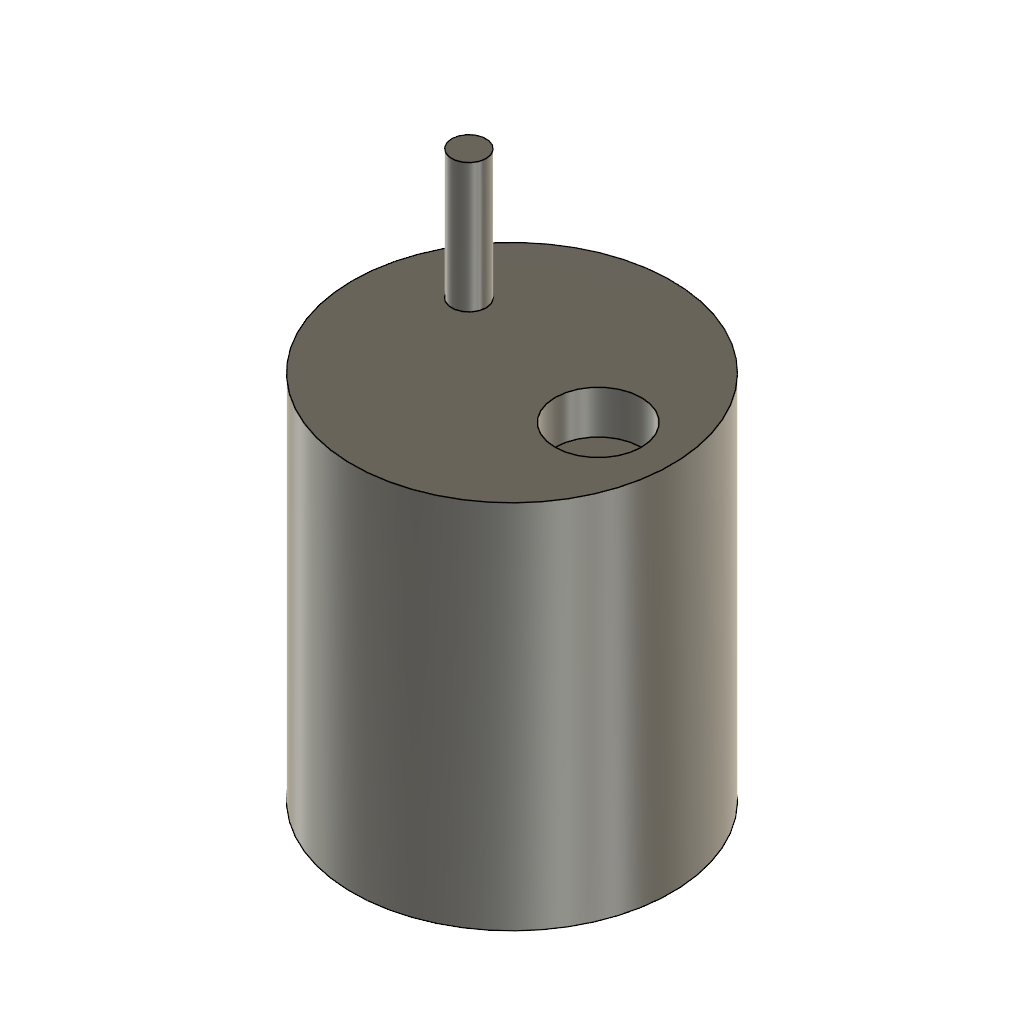
02-26 Humidifier Placeholder (Autodesk Fusion 360 design; units mm, degrees)
part number: 2026-11-09-09-40-40-626
Autodesk Fusion 360 part; units mm, degrees
sketch "Sketch1" plane through (0, 0, 0) normal (0, 0, 1) x (1, 0, 0)
  circle A0 centre (0, 0) radius 18.5
  dimension "d1" = 37
  constraint coincident A0.centre origin
  measures "d1" diameter of A0
extrude "Extrude1" add sketch "Sketch1" along normal blind 43
sketch "Sketch2" plane through (0, 0, 43) normal (0, 0, 1) x (-1, 0, 0)
  circle A0 centre (0, 0) radius 18.5
  circle A1 centre (-10, 0) radius 5
  dimension "d4" = 10
  dimension "d5" = 10
  measures "d4" diameter of A1
  measures "d5" distance of A0.centre A1.centre
extrude "Extrude2" cut sketch "Sketch2" against normal blind 5 contours A1
sketch "Sketch3" plane through (0, 0, 43) normal (0, 0, 1) x (-1, 0, 0)
  circle A0 centre (-10, 0) radius 5
  circle A1 centre (0, 0) radius 18.5
  circle A2 centre (10, -5) radius 2
  dimension "d8" = 4
  measures "d8" diameter of A2
extrude "Extrude3" add sketch "Sketch3" along normal blind 15 contours A2
